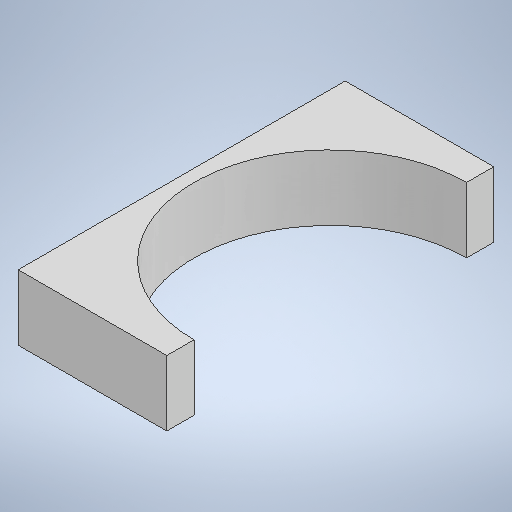
# Autodesk Inventor part: manivela_p1
Saved by Autodesk Inventor 2025.2 (Build 292293000, 293)
## iProperties
Created: 2025-03-19
Part Number: manivela_p1
Material: Generic
Document SubType Name: Modeling
Designer: laura
Density: 1 g/cm^3
Appearance: Default
Author: laura
Autodesk Inventor part; units mm, degrees
ref_plane "YZ Plane" through (0, 0, 0) normal (1, 0, 0) x (0, 1, 0)
ref_plane "XZ Plane" through (0, 0, 0) normal (0, 1, 0) x (-1, 0, 0)
sketch "Sketch1" plane through (0, 0, 0) normal (0, 0, 1) x (1, 0, 0)
  line L0 (-20, 0) -> (0, 0)
  line L1 (0, 0) -> (6.5, 0)
  line L2 (6.5, 0) -> (6.5, 3)
  line L3 (6.5, 3) -> (-0.3153, 3)
  line L4 (-0.3153, 3) -> (-19.4412, 3)
  line L5 (-19.4412, 3) -> (-49.4412, 3)
  line L6 (-49.4412, 3) -> (-49.4412, 0)
  line L7 (-49.4412, 0) -> (-20, 0)
  line L8 (-20, 0) -> (6.5, 0) construction
  line L9 (6.5, 0) -> (6.5, 0) construction
  dimension "d0" = 3
  dimension "d1" = 3
  dimension "d2" = 3
  dimension "d5" = 6.5
  dimension "d6" = 20
  dimension "d7" = 30
  dimension "d25" = 0
  constraints: 20 end point, 4 perpendicular, 2 vertical, 1 collinear, 1 horizontal, 1 parallel
  measures "d0" distance between parallel lines of L1 L3
  measures "d1" distance between parallel lines of L0 L4
  measures "d2" distance between parallel lines of L7 L5
  measures "d5" distance of L1.end L0.end
  measures "d6" distance of L0.start L0.end
  measures "d7" distance of L4.end L5.end
  measures "d25" distance between parallel lines of L8 L0
extrude "Extrusion1" add sketch "Sketch1" along normal blind 15
ref_plane "Work Plane1" through (6.5, 3, 15) normal (0, -1, 0) x (-1, 0, 0)
sketch "Sketch2" plane through (6.5, 3, 15) normal (0, -1, 0) x (-1, 0, 0)
  line L0 (0, 15) -> (0, 0) projected
  line L1 (0, 0) -> (55.9412, 3.5)
  line L2 (55.9412, 15) -> (55.9412, 0) projected
  line L3 (0, 7.5) -> (55.9412, 7.5)
  line L4 (0, 15) -> (55.9412, 11.5)
  line L5 (0, 0) -> (55.9412, 0) projected
  line L6 (6.8153, 0) -> (45.9412, 0) projected
  line L7 (45.9412, 0) -> (55.9412, 0) projected
  line L8 (45.9412, 15) -> (55.9412, 15) projected
  line L9 (6.8153, 15) -> (45.9412, 15) projected
  line L10 (0, 15) -> (55.9412, 15) projected
  line L11 (6.8153, 15) -> (6.8153, 0) projected
  line L12 (45.9412, 15) -> (45.9412, 0) projected
  circle A0 centre (20, 7.5) radius 2
  line L13 (0, 15) -> (0, 0) projected
  arc A1 (55.9412, 7.5) -> (51.949, 11.7498) centre (51.6831, 7.5) ccw
  arc A2 (51.949, 3.2502) -> (55.9412, 7.5) centre (51.6831, 7.5) ccw
  circle A3 centre (51.6831, 7.5) radius 1.5
  point P0 (6.5, 15)
  point P1 (0, 15)
  point P2 (45.9412, 12.1257)
  point P3 (61.3258, 15)
  point P4 (65.9412, 15)
  dimension "d10" = 15
  dimension "d11" = 8
  dimension "d17" = 20
  dimension "d18" = 4
  dimension "d26" = 3
  constraints: 6 end point, 6 point on line, 4 centre point, 4 point on circle, 3 midpoint, 2 coincident, 2 symmetric about line, 1 tangent
  measures "d10" diameter of L1.start L3
  measures "d11" diameter of L1.end L3
  measures "d17" distance of A0.centre point (0, 7.5)
  measures "d18" diameter of A0
  measures "d26" diameter of A3
extrude "Extrusion2" cut sketch "Sketch2" along normal through all contours L11 L9 L12 L4 | L4 L12 L3 A0 L11 | L3 A0 L12 L1 L11 | L12 L8 L2 L4 | L4 A1 L3 A3 L12 | L1 L12 L5 L11 | A0 L3 | L3 A0 | L4 L2 A1 | L3 A3 A2 L1 L12 | L1 L2 L5 L12 | L2 L1 A2 | A3 L3 | L3 A3
sketch "Sketch3" plane through (-0.3153, 3, 14.6859) normal (0, 1, 0) x (1, 0, 0)
  line L0 (6.8153, 14.6859) -> (6.8153, -0.3141) projected
  circle A0 centre (6.8153, 7.1859) radius 6.25
  point P0 (6.8153, 0.9359)
  point P1 (6.8153, 13.4359)
  dimension "d14" = 12.5
  constraints: 1 centre point, 1 midpoint
  measures "d14" diameter of A0
extrude "Extrusion3" cut sketch "Sketch3" against normal through all contours L0 A0 picked at (5.4338, 5.6265)
extrude "Extrusion4" cut sketch "Sketch2" along normal through all contours A0 L3 | L3 A0
extrude "Extrusion6" cut sketch "Sketch2" along normal through all contours L11 L9 L12 L4 | L4 L12 L3 A0 L11 | L3 A0 L12 L1 L11 | L12 L8 L2 L4 | L4 A1 L3 A3 L12 | L1 L12 L5 L11 | A0 L3 | L3 A0 | L4 L2 A1 | L3 A3 A2 L1 L12 | L1 L2 L5 L12 | L2 L1 A2 | A3 L3 | L3 A3
body "Solid1"
